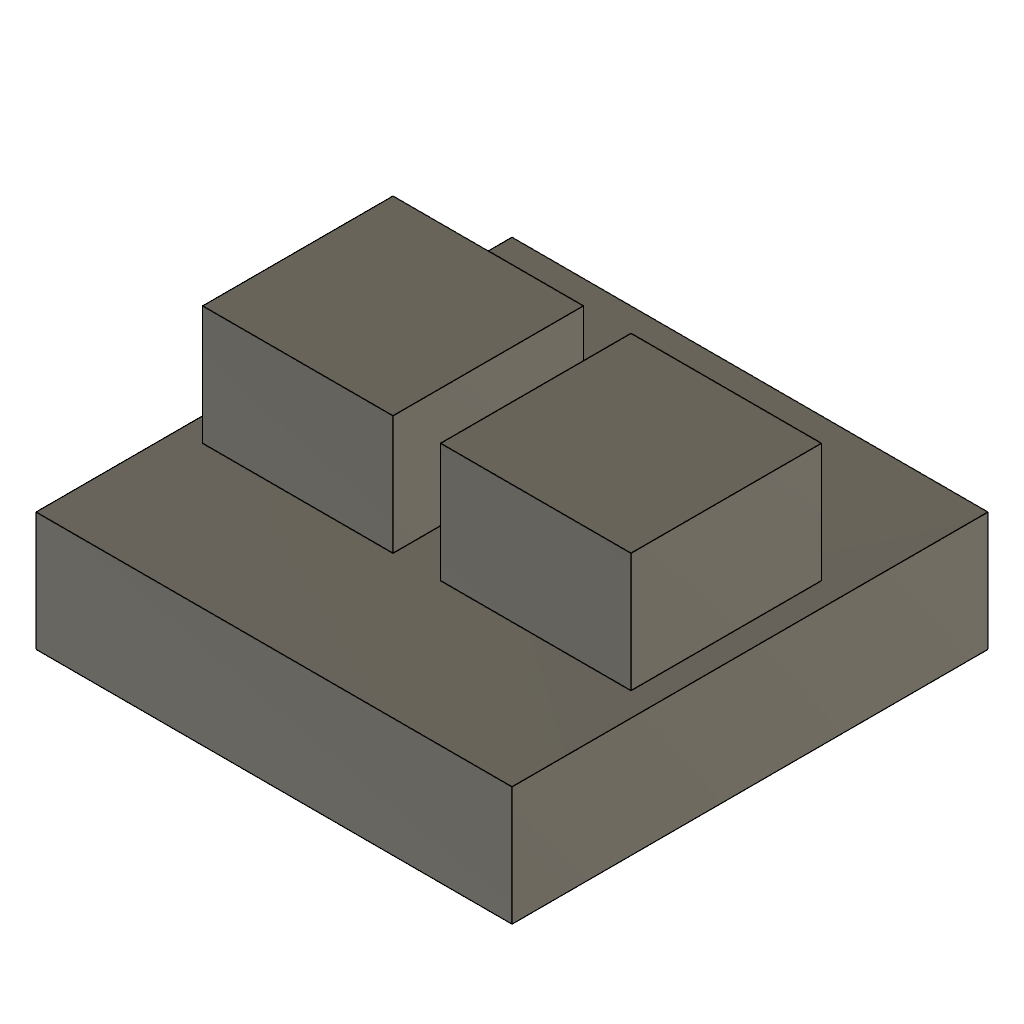
combine_cross_component (Autodesk Fusion 360 design; units mm, degrees)
Autodesk Fusion 360 part; units mm, degrees
sketch "Sketch1" plane through (0, 0, 0) normal (0, 0, 1) x (1, 0, 0) in component "Comp1"
  line L0 (-20, -20) -> (20, -20)
  line L1 (20, -20) -> (20, 20)
  line L2 (20, 20) -> (-20, 20)
  line L3 (-20, 20) -> (-20, -20)
extrude "Extrude1" add sketch "Sketch1" along normal blind 10 makes body 1 in component "Comp1"
sketch "Sketch2" plane through (0, 0, 0) normal (0, 0, 1) x (1, 0, 0) in component "Comp1"
  line L0 (2, -8) -> (18, -8)
  line L1 (18, -8) -> (18, 8)
  line L2 (18, 8) -> (2, 8)
  line L3 (2, 8) -> (2, -8)
extrude "Extrude2" add sketch "Sketch2" along normal blind 20 separate body makes body 2 in component "Comp1"
sketch "Sketch1 (2)" plane through (0, 0, 0) normal (0, 0, 1) x (1, 0, 0) in component "Comp2"
  line L0 (-18, -8) -> (-2, -8)
  line L1 (-2, -8) -> (-2, 8)
  line L2 (-2, 8) -> (-18, 8)
  line L3 (-18, 8) -> (-18, -8)
extrude "Extrude1'" add sketch "Sketch1 (2)" along normal blind 20 separate body makes body 3 in component "Comp2"
combine "Combine1" operation add target body 1 tool bodies 3 2 in component "Comp1"
component "Comp1" placed x (1, 0, 0) y (0, 1, 0) z (0, 0, 1) at (0, 0, 0)
component "Comp2" placed x (1, 0, 0) y (0, 1, 0) z (0, 0, 1) at (0, 0, 0)
named bodies: "B2", "B1"
